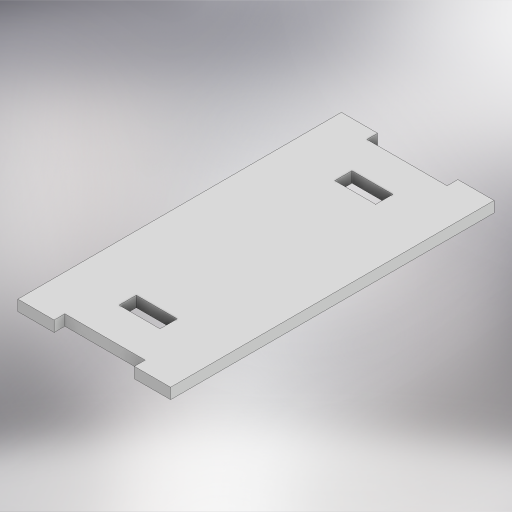
# Autodesk Inventor part: batt_holder
Saved by Autodesk Inventor 2023.5 (Build 275446000, 446)
## iProperties
Created: 2026-10-31
Part Number: batt_holder
Material: Generic
Document SubType Name: Modeling
Designer: WORKPLUS
Density: 1 g/cm^3
Appearance: Default
Author: WORKPLUS
Autodesk Inventor part; units mm, degrees
ref_plane "YZ Plane" through (0, 0, 0) normal (1, 0, 0) x (0, 1, 0)
ref_plane "XZ Plane" through (0, 0, 0) normal (0, 1, 0) x (-1, 0, 0)
ref_plane "XY Plane" through (0, 0, 0) normal (0, 0, 1) x (1, 0, 0)
sketch "Sketch1" plane through (0, 0, 0) normal (0, 1, 0) x (-1, 0, 0)
  line L0 (-35.4, 70) -> (35.4, 70)
  line L1 (35.4, 70) -> (35.4, -70)
  line L2 (35.4, -70) -> (-35.4, -70)
  line L3 (-35.4, -70) -> (-35.4, 70)
  line L4 (-35.4, 70) -> (35.4, -70) construction
  line L5 (35.4, 70) -> (-35.4, -70) construction
  line L6 (35.4, 70) -> (-35.4, 70)
  line L7 (-35.4, 70) -> (-35.4, 75)
  line L8 (35.4, 75) -> (35.4, 70)
  line L9 (-35.4, -70) -> (-35.4, -75)
  line L10 (35.4, -75) -> (35.4, -70)
  line L11 (35.4, 70) -> (18.614, 70)
  line L12 (18.614, 70) -> (18.614, 75)
  line L13 (18.614, 75) -> (35.4, 75)
  line L14 (35.4, 75) -> (35.4, 70)
  line L15 (-35.4, 75) -> (-18.614, 75)
  line L16 (-18.614, 75) -> (-18.614, 70)
  line L17 (-18.614, 70) -> (-35.4, 70)
  line L18 (-35.4, 70) -> (-35.4, 75)
  line L19 (-35.4, -75) -> (-18.614, -75)
  line L20 (-18.614, -75) -> (-18.614, -70)
  line L21 (-18.614, -70) -> (-35.4, -70)
  line L22 (-35.4, -70) -> (-35.4, -75)
  line L23 (35.4, -75) -> (18.614, -75)
  line L24 (18.614, -75) -> (18.614, -70)
  line L25 (18.614, -70) -> (35.4, -70)
  line L26 (35.4, -70) -> (35.4, -75)
  line L27 (-35.4, 75) -> (-18.614, 75)
  line L28 (18.614, 75) -> (35.4, 75)
  line L29 (35.4, -70) -> (18.614, -70)
  line L30 (-18.614, -70) -> (-35.4, -70)
  line L31 (-35.4, -75) -> (-18.614, -75)
  line L32 (18.614, -75) -> (35.4, -75)
  point P0 (0, 0)
  dimension "d0" = 70.8
  dimension "d1" = 140
  dimension "d2" = 70.8
  dimension "d3" = 5
  dimension "d4" = 70.8
  dimension "d5" = 5
  dimension "d6" = 16.786
  dimension "d7" = 16.786
  dimension "d8" = 16.786
  dimension "d9" = 16.786
  constraints: 66 end point, 18 parallel, 8 horizontal, 8 perpendicular, 2 midpoint, 1 point on line
  measures "d0" distance between parallel lines of L3 L1
  measures "d1" distance of L0.end L1.end
  measures "d2" distance of L7.end L8.start
  measures "d3" distance of L6.end L7.end
  measures "d4" distance of L10.start L9.end
  measures "d5" distance of L9.end L9.start
  measures "d6" distance of L12.end L13.end
  measures "d7" distance of L16.end L17.end
  measures "d8" distance of L21.end L20.end
  measures "d9" distance of L24.end L25.end
extrude "Extrusion1" add sketch "Sketch1" along normal blind 5
sketch "Sketch2" plane through (0, 5, 0) normal (0, 1, 0) x (1, 0, 0)
  line L0 (-18.614, -70) -> (18.614, -70) projected
  line L1 (0, -70) -> (0, -50)
  line L2 (-9.5, -54) -> (9.5, -54)
  line L3 (9.5, -54) -> (9.5, -46)
  line L4 (9.5, -46) -> (-9.5, -46)
  line L5 (-9.5, -46) -> (-9.5, -54)
  line L6 (-9.5, -54) -> (9.5, -46) construction
  line L7 (9.5, -54) -> (-9.5, -46) construction
  line L8 (-12.28, 0) -> (14.9876, 0)
  line L9 (-9.5, 54) -> (9.5, 54)
  line L10 (9.5, 54) -> (9.5, 46)
  line L11 (9.5, 46) -> (-9.5, 46)
  line L12 (-9.5, 46) -> (-9.5, 54)
  line L13 (9.5, 54) -> (-9.5, 46) construction
  point P0 (0, 0)
  dimension "d12" = 20
  dimension "d13" = 19
  dimension "d14" = 8
  constraints: 26 end point, 4 symmetric about line, 3 midpoint, 2 horizontal, 2 parallel, 1 perpendicular, 1 vertical
  measures "d12" distance of L1.start L1.end
  measures "d13" distance of L3.end L4.end
  measures "d14" distance of L2.end L3.end
extrude "Extrusion2" cut sketch "Sketch2" against normal blind 70.75
body "Solid1"
